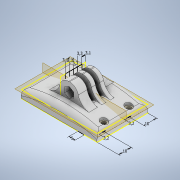
# Autodesk Inventor part: deasupra
Saved by Autodesk Inventor 2022.6 (Build 266554000, 554)
## iProperties
Created: 2026-06-26
Part Number: deasupra
Material: Generic
Document SubType Name: Modeling
Designer: Dragos Macovei
Density: 1 g/cm^3
Appearance: Default
Author: Dragos Macovei
Autodesk Inventor part; units mm, degrees
ref_plane "YZ Plane" through (0, 0, 0) normal (1, 0, 0) x (0, 1, 0)
ref_plane "XY Plane" through (0, 0, 0) normal (0, 0, 1) x (1, 0, 0)
sketch "Sketch1" plane through (0, 0, 0) normal (0, 1, 0) x (-1, 0, 0)
  line L0 (0, 0) -> (60, 0)
  line L1 (60, 0) -> (60, 40)
  line L2 (60, 40) -> (0, 40)
  line L3 (0, 40) -> (0, 0)
  dimension "d0" = 60
  dimension "d1" = 40
  constraints: 8 end point, 2 parallel, 1 horizontal, 1 perpendicular
  measures "d0" distance of L2.end L1.end
  measures "d1" distance of L1.end L0.end
extrude "Extrusion1" add sketch "Sketch1" along normal blind 6
sketch "Sketch3" plane through (-60, 0, 0) normal (-1, 0, 0) x (0, 0, 1)
  line L0 (0, 0) -> (40, 0) projected
  line L1 (40, 0) -> (40, 6) projected
  line L2 (0, 6) -> (40, 6) projected
  line L3 (0, 0) -> (0, 6) projected
  circle A0 centre (20.5277, -133.4302) radius 135
  point P0 (40, 0.1581)
  dimension "d6" = 270
  constraints: 3 other
extrude "Extrusion2" cut sketch "Sketch3" against normal blind 45 contours A0 L1 L0 picked at (17.7687, 0.4588)
sketch "Sketch4" plane through (0, 0, 0) normal (0, -1, 0) x (1, 0, 0)
  line L0 (-15, 40) -> (-15, 0) projected
  line L1 (0, 0) -> (-15, 0) projected
  line L2 (0, 40) -> (0, 0) projected
  line L3 (-15, 40) -> (0, 40) projected
  line L4 (-60, 40) -> (0, 40) projected
  line L5 (-15, 0) -> (-10, 0)
  line L6 (-10, 0) -> (-10, 40)
  line L7 (-10, 40) -> (-15, 40)
  line L8 (-15, 40) -> (-15, 0)
  dimension "d10" = 5
  constraints: 8 end point, 2 parallel, 1 horizontal, 1 perpendicular, 1 point on line
  measures "d10" distance of L7.end L6.end
sketch "Sketch5" plane through (0, 0, 0) normal (0, -1, 0) x (1, 0, 0)
  line L0 (0, 0) -> (-15, 0) projected
  line L1 (0, 40) -> (0, 0) projected
  line L2 (-15, 40) -> (0, 40) projected
  line L3 (-60, 40) -> (0, 40) construction
  line L4 (-4.5, 40) -> (-4.5, 0) construction
  line L5 (0, 0) -> (-15, 0) construction
  circle A0 centre (-4.5, 30) radius 1.6
  circle A1 centre (-4.5, 10) radius 1.6
  line L6 (-15, 40) -> (-15, 0) projected
  point P0 (-10, 40)
  point P1 (-10, 0)
  point P2 (-4.5, 20)
  point P3 (-9, 0)
  dimension "d14" = 10
  dimension "d15" = 10
  dimension "d16" = 3.2
  dimension "d17" = 3.2
  constraints: 4 point on line, 2 centre point, 2 coincident, 2 end point, 1 midpoint
  measures "d14" distance from line of L0 point (-4.5, 10)
  measures "d15" distance from line of L2 point (-4.5, 30)
  measures "d16" diameter of A0
  measures "d17" diameter of A1
extrude "Extrusion4" cut sketch "Sketch5" along normal through all both and the other way through all contours A0 | A1
sketch "Sketch7" plane through (0, 6, 0) normal (0, 1, 0) x (1, 0, 0)
  line L0 (-60, 0) -> (-60, -40) projected
  line L1 (-60, -40) -> (0, -40) projected
  line L2 (0, -40) -> (0, 0) projected
  line L3 (0, 0) -> (-60, 0) projected
ref_plane "Work Plane1" through (-60, 6, 20) normal (0, 0, 1) x (1, 0, 0)
sketch "Sketch8" plane through (-60, 6, 20) normal (0, 0, 1) x (1, 0, 0)
  point P0 (60, -6)
sketch "Sketch9" plane through (-60, 6, 20) normal (0, 0, 1) x (1, 0, 0)
  line L0 (0, 0) -> (60, 0) projected
  line L1 (0, -5.8419) -> (0, 0) projected
  line L2 (23, 16.5) -> (37, 16.5)
  line L3 (37, 16.5) -> (37, 0)
  line L4 (37, 0) -> (23, 0)
  line L5 (23, 0) -> (23, 16.5)
  point P0 (60, -6)
  point P1 (30, 0)
  point P2 (30, 0)
  point P3 (30, 0)
  point P4 (23, 0)
  dimension "d25" = 30
  dimension "d26" = 7
  dimension "d27" = 7
  dimension "d28" = 16.5
  constraints: 8 end point, 3 midpoint, 2 parallel, 1 horizontal, 1 perpendicular, 1 point on line
  measures "d25" distance from line of L1 point (30, 0)
  measures "d26" distance from line of point (30, 0) L3
  measures "d27" distance from line of L5 point (30, 0)
  measures "d28" distance between parallel lines of L0 L2
extrude "Extrusion6" add sketch "Sketch9" along normal blind 12 and the other way blind 8
sketch "Sketch10" plane through (-60, 6, 32) normal (0, 0, 1) x (1, 0, 0)
  line L0 (23, 16.5) -> (23, 0) projected
  line L1 (37, 0) -> (23, 0) projected
  line L2 (37, 0) -> (37, 16.5) projected
  line L3 (37, 16.5) -> (23, 16.5) projected
  circle A0 centre (30, 9) radius 2.575
  point P0 (60, -6)
  dimension "d31" = 9
  dimension "d32" = 5.15
  constraints: 1 centre point
  measures "d31" distance from line of L1 A0.centre
  measures "d32" diameter of A0
extrude "Extrusion7" cut sketch "Sketch10" against normal through all contours A0
sketch "Sketch11" plane through (-60, 6, 32) normal (0, 0, 1) x (1, 0, 0)
  point P0 (60, -6)
sketch "Sketch12" plane through (-37, 6, 32) normal (-1, 0, 0) x (0, 0, 1)
  line L0 (0, 11.575) -> (-20, 11.575) projected
  line L1 (0, 0) -> (-20, 0) projected
  line L2 (0, 16.5) -> (0, 0) projected
  line L3 (0, 16.5) -> (-20, 16.5) projected
  line L4 (-20, 0) -> (-20, 16.5) projected
  line L5 (-20, 16.5) -> (0, 16.5) projected
  line L6 (-13.6, 16.5) -> (-10.3, 16.5)
  line L7 (-10.3, 16.5) -> (-10.3, 0)
  line L8 (-10.3, 0) -> (-13.6, 0)
  line L9 (-13.6, 0) -> (-13.6, 16.5)
  line L10 (-20, 0) -> (0, 0) projected
  line L11 (-10.3, 16.5) -> (-7, 16.5)
  line L12 (-7, 16.5) -> (-7, 0)
  line L13 (-7, 0) -> (-10.3, 0)
  line L14 (-10.3, 0) -> (-10.3, 16.5)
  line L15 (-13.6, 16.5) -> (-16.9, 16.5)
  line L16 (-16.9, 16.5) -> (-16.9, 0)
  line L17 (-16.9, 0) -> (-13.6, 0)
  line L18 (-13.6, 0) -> (-13.6, 16.5)
  line L19 (0, 0) -> (-20, 0) projected
  line L20 (-7, 16.5) -> (-3.9, 16.5)
  line L21 (-3.9, 16.5) -> (-3.9, 0)
  line L22 (-3.9, 0) -> (-7, 0)
  line L23 (-7, 0) -> (-7, 16.5)
  line L24 (0, 16.5) -> (-20, 16.5) projected
  point P0 (-32, -6)
  point P1 (-13.6, 0)
  dimension "d35" = 3.3
  dimension "d36" = 3.3
  dimension "d37" = 3.3
  dimension "d38" = 3.1
  dimension "d39" = 3.1
  constraints: 32 end point, 8 parallel, 4 horizontal, 4 perpendicular, 4 point on line, 2 other
  measures "d35" distance between parallel lines of L7 L9
  measures "d36" distance between parallel lines of L12 L7
  measures "d37" distance between parallel lines of L9 L16
  measures "d38" distance between parallel lines of L16 L4
  measures "d39" distance between parallel lines of L21 L12
extrude "Extrusion8" cut sketch "Sketch12" against normal through all contours L12 L1 L7 L0 | L0 L7 L3 L12 | L9 L1 L16 L0 | L0 L16 L3 L9
sketch "Sketch14" plane through (0, 6, 0) normal (0, 0, -1) x (-1, 0, 0)
  line L0 (60, -5.8419) -> (60, 0) projected
  line L1 (0, -6) -> (0, 0) projected
  arc A0 (60, 0) -> (0, 0) centre (30, -102.9346) ccw
  line L2 (60, 0) -> (0, 0)
  constraints: 2 end point, 2 point on circle, 1 centre point, 1 horizontal
extrude "Extrusion10" add sketch "Sketch14" against normal up to surface (40 mm away)
sketch "Sketch13" plane through (-60, 6, 32) normal (0, 0, 1) x (1, 0, 0)
  circle A0 centre (30, 9) radius 2.575 projected
  line L0 (23, 16.5) -> (23, 4.0539) projected
  line L1 (37, 4.0539) -> (37, 16.5) projected
  line L2 (37, 16.5) -> (23, 16.5) projected
  line L3 (30, 13.2147) -> (33.65, 11.1073)
  line L4 (33.65, 11.1073) -> (33.65, 6.8927)
  line L5 (33.65, 6.8927) -> (30, 4.7853)
  line L6 (30, 4.7853) -> (26.35, 6.8927)
  line L7 (26.35, 6.8927) -> (26.35, 11.1073)
  line L8 (26.35, 11.1073) -> (30, 13.2147)
  arc A1 (37, 4.0539) -> (23, 4.0539) centre (30, -102.9346) ccw projected
  point P0 (60, -6)
  dimension "d44" = 7.3
  constraints: 12 end point, 1 coincident, 13 other
  measures "d44" distance between parallel lines of L4 L7
extrude "Extrusion9" cut sketch "Sketch13" against normal blind 4 contours L3 L4 L5 L6 L7 L8
extrude "Extrusion11" cut sketch "Sketch12" against normal up to surface (14 mm away) contours L12 L1 L7 L0 | L0 L7 L3 L12 | L9 L1 L16 L0 | L0 L16 L3 L9
fillet "Fillet4" radius 10 6 edges at (-23, 10.0539, 28.5) (-23, 10.0539, 20.05) (-23, 10.0539, 13.55) (-37, 10.0539, 13.55) (-37, 10.0539, 20.05) (-37, 10.0539, 28.5)
fillet "Fillet5" radius 7 6 edges at (-37, 22.5, 28.5) (-37, 22.5, 20.05) (-37, 22.5, 13.55) (-23, 22.5, 13.55) (-23, 22.5, 20.05) (-23, 22.5, 28.5)
fillet "Fillet6" radius 4 4 edges at (-23, 10.0539, 16.75) (-23, 10.0539, 23.35) (-37, 10.0539, 16.75) (-37, 10.0539, 23.35)
fillet "Fillet7" radius 4 4 edges at (-60, 6, 20) (-30, 10.2826, 0) (-30, 10.2826, 40) (0, 6, 20)
extrude "Extrusion12" cut sketch "Sketch5" along normal through all both and the other way through all contours A0 | A1
ref_plane "Work Plane2" through (0, 6, 0) normal (0, 1, 0) x (-1, 0, 0)
sketch "Sketch15" plane through (0, 6, 0) normal (0, 1, 0) x (-1, 0, 0)
  line L0 (41.4143, 21.7) -> (41.4143, 25) projected
  line L1 (41.4143, 21.7) -> (45.5497, 21.7) projected
  line L2 (45.5497, 18.4) -> (45.5497, 21.7) projected
  line L3 (45.5497, 18.4) -> (41.4143, 18.4) projected
  line L4 (41.4143, 15.1) -> (41.4143, 18.4) projected
  line L5 (41.4143, 15.1) -> (45.5497, 15.1) projected
  line L6 (45.5497, 12) -> (45.5497, 15.1) projected
  line L7 (14.4503, 12) -> (45.5497, 12) projected
  line L8 (14.4503, 15.1) -> (14.4503, 12) projected
  line L9 (14.4503, 15.1) -> (18.5857, 15.1) projected
  line L10 (18.5857, 18.4) -> (18.5857, 15.1) projected
  line L11 (18.5857, 18.4) -> (14.4503, 18.4) projected
  line L12 (14.4503, 21.7) -> (14.4503, 18.4) projected
  line L13 (14.4503, 21.7) -> (18.5857, 21.7) projected
  line L14 (18.5857, 25) -> (18.5857, 21.7) projected
  line L15 (18.5857, 25) -> (14.4503, 25) projected
  line L16 (14.4503, 32) -> (14.4503, 25) projected
  line L17 (45.5497, 32) -> (14.4503, 32) projected
  line L18 (45.5497, 25) -> (45.5497, 32) projected
  line L19 (45.5497, 25) -> (41.4143, 25) projected
  line L20 (2.9924, 4) -> (2.9924, 9.4641) projected
  line L21 (57.0076, 4) -> (2.9924, 4) projected
  line L22 (57.0076, 36) -> (57.0076, 4) projected
  line L23 (2.9924, 36) -> (57.0076, 36) projected
  circle A0 centre (4.5, 30) radius 2.75
  circle A1 centre (5, 10) radius 2.75
  line L24 (2.9924, 30.5359) -> (2.9924, 36) projected
  line L25 (2.9924, 10.5359) -> (2.9924, 29.4641) projected
  point P0 (0, 0)
  point P1 (3.4, 10)
  point P2 (3.4, 30)
  dimension "d60" = 5.5
  dimension "d61" = 5.5
  constraints: 2 centre point, 2 vertical alignment, 1 coincident, 2 other
  measures "d60" diameter of A0
  measures "d61" diameter of A1
extrude "Extrusion13" cut sketch "Sketch15" along normal blind 3 contours A1 | A0
sketch "Sketch16" plane through (-60, 6, 12) normal (0, 0, -1) x (-1, 0, 0)
  arc A0 (-30.3734, 16.5) -> (-37.2196, 10.959) centre (-30.3734, 9.5) ccw projected
  arc A1 (-45.5497, 3.149) -> (-37.2196, 10.959) centre (-47, 13.0433) ccw projected
  arc A2 (-14.4503, 3.149) -> (-45.5497, 3.149) centre (-30, -102.9346) ccw projected
  arc A3 (-22.7804, 10.959) -> (-14.4503, 3.149) centre (-13, 13.0433) ccw projected
  arc A4 (-22.7804, 10.959) -> (-29.6266, 16.5) centre (-29.6266, 9.5) ccw projected
  line L0 (-29.6266, 16.5) -> (-30.3734, 16.5) projected
  circle A5 centre (-30, 9) radius 2.575 projected
  circle A6 centre (-30, 9) radius 7.5
  point P0 (-60, -6)
  point P1 (-22.6091, 10.2749)
  point P2 (-22.8651, 11.3115)
  point P3 (-37.1349, 11.3115)
  point P4 (-37.3909, 10.2749)
  constraints: 1 centre point, 1 coincident
extrude "Extrusion14" cut sketch "Sketch16" along normal blind 43 contours A6 A4 A3 A2 A1 A0 | A2 A6
fillet "Fillet8" radius 1 1 edges at (-15, 1.5688, 19.9941)
body "Solid1"
